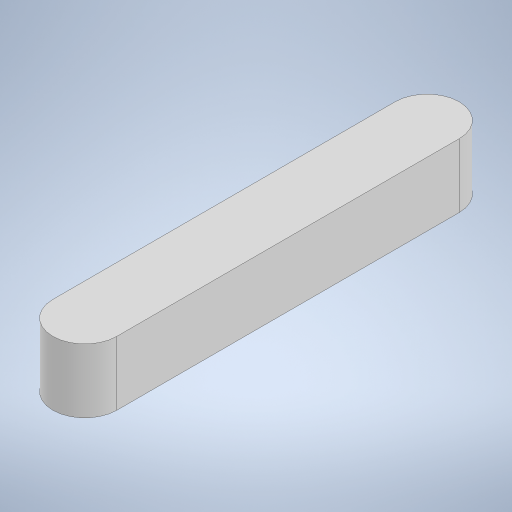
# Autodesk Inventor part: KeyG1
Saved by Autodesk Inventor 2023 (Build 270158000, 158)
## iProperties
Created: 2024-05-11
Part Number: KeyG1
Material: Generic
Document SubType Name: Modeling
Designer: BenFr
Density: 1 g/cm^3
Appearance: Default
Author: BenFr
Autodesk Inventor part; units mm, degrees
ref_plane "YZ Plane" through (0, 0, 0) normal (1, 0, 0) x (0, 1, 0)
ref_plane "XZ Plane" through (0, 0, 0) normal (0, 1, 0) x (-1, 0, 0)
ref_plane "XY Plane" through (0, 0, 0) normal (0, 0, 1) x (1, 0, 0)
sketch "Sketch1" plane through (0, 0, 0) normal (0, 1, 0) x (-1, 0, 0)
  line L0 (-2.5, 15.875) -> (2.5, 15.875)
  line L1 (2.5, 15.875) -> (2.5, -15.875)
  line L2 (2.5, -15.875) -> (-2.5, -15.875)
  line L3 (-2.5, -15.875) -> (-2.5, 15.875)
  line L4 (-2.5, 15.875) -> (2.5, -15.875) construction
  line L5 (2.5, 15.875) -> (-2.5, -15.875) construction
  point P0 (0, 0)
  dimension "d0" = 5
  dimension "d1" = 31.75
  constraints: 12 end point, 2 midpoint, 2 parallel, 1 horizontal, 1 perpendicular
  measures "d0" distance of L1.end L2.end
  measures "d1" distance of L0.end L1.end
extrude "Extrusion1" add sketch "Sketch1" along normal blind 5
fillet "Fillet1" radius 2.5 4 edges at (-2.5, 2.5, 15.875) (2.5, 2.5, 15.875) (2.5, 2.5, -15.875) (-2.5, 2.5, -15.875)
body "Solid1"
